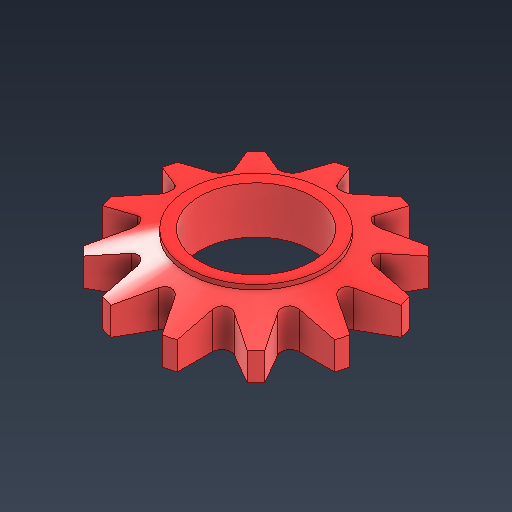
# Autodesk Inventor part: Nut
Saved by Autodesk Inventor 2026.4 (Build 304435000, 435)
## iProperties
Created: 2026-11-10
Part Number: Nut
Material: Generic
Document SubType Name: Modeling
Designer: YmCris
Density: 1 g/cm^3
Appearance: Light Red
Author: YmCris
Autodesk Inventor part; units mm, degrees
ref_plane "YZ Plane" through (0, 0, 0) normal (1, 0, 0) x (0, 1, 0)
ref_plane "XZ Plane" through (0, 0, 0) normal (0, 1, 0) x (-1, 0, 0)
ref_plane "XY Plane" through (0, 0, 0) normal (0, 0, 1) x (1, 0, 0)
sketch "Sketch1" plane through (0, 0, 0) normal (0, 1, 0) x (-1, 0, 0)
  circle A0 centre (0, 0) radius 26
  circle A1 centre (0, 0) radius 12
  dimension "d0" = 52
  dimension "d1" = 24
  constraints: 2 centre point, 2 coincident
  measures "d0" diameter of A0
  measures "d1" diameter of A1
extrude "Extrusion1" add sketch "Sketch1" along normal blind 9
sketch "Sketch2" plane through (0, 9, 0) normal (0, 1, 0) x (1, 0, 0)
  circle A0 centre (0, 0) radius 14.5
  circle A1 centre (0, 0) radius 12
  dimension "d4" = 29
  constraints: 2 centre point, 2 coincident
  measures "d4" diameter of A0
extrude "Extrusion2" add sketch "Sketch2" along normal blind 1
sketch "Sketch3" plane through (0, 9, 0) normal (0, 1, 0) x (1, 0, 0)
  arc A0 (-19, -1.7321) -> (-19, 1.7321) centre (-20, 0) ccw
  line L0 (-25.4243, -5.4411) -> (-19, -1.7321)
  circle A1 centre (0, 0) radius 26 construction
  line L1 (-26, 0) -> (0, 0) construction
  line L2 (-25.4243, 5.4411) -> (-19, 1.7321)
  arc A2 (-25.4243, 5.4411) -> (-25.4243, -5.4411) centre (0, 0) ccw
  point P0 (-26.8858, -6.2849)
  point P1 (-26.8858, 6.2849)
  dimension "d7" = 4
  dimension "d8" = 20
  dimension "d9" = 30
  dimension "d10" = 30
  constraints: 7 point on circle, 6 end point, 2 centre point, 2 symmetric about line, 1 coincident, 1 horizontal, 1 horizontal alignment, 1 tangent
  measures "d7" diameter of A0
  measures "d8" distance of point (0, 0) A0.centre
  measures "d9" angle of L0 L1
  measures "d10" angle of L1 L2
extrude "Extrusion3" cut sketch "Sketch3" against normal blind 9
pattern_circular "Circular Pattern1" count 12 over 360 about axis through (0, 0, 0) along (0, 1, 0) of "Extrusion3"
sketch "Sketch4" plane through (0, 0, 0) normal (0, 0, 1) x (1, 0, 0)
  line L0 (14.5, 9) -> (14.5, 10) projected
  line L1 (14.5, 9) -> (33.1603, 4)
  line L2 (33.1603, 4) -> (33.1603, 9)
  line L3 (33.1603, 9) -> (14.5, 9)
  line L4 (0, 0) -> (0, 12.8853) construction
  dimension "d16" = 15
  dimension "d17" = 5
  constraints: 8 end point, 2 vertical, 1 perpendicular
  measures "d16" angle of L1 L3
  measures "d17" distance of L1.end L2.end
revolve "Revolution1" cut sketch "Sketch4" angle 360 about axis through (0, 0, 0) along (0, 1, 0)
body "Solid1"
